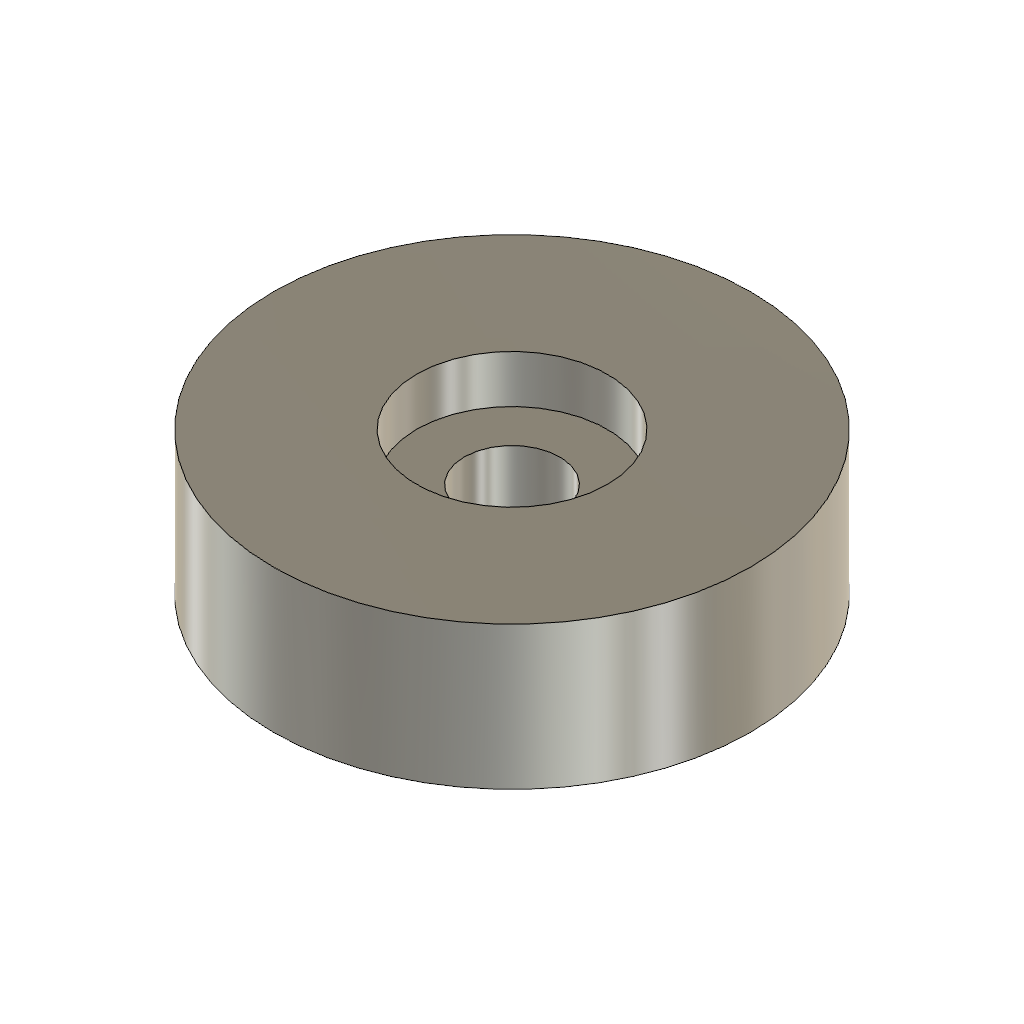
vendor_MultiDiscPart (Autodesk Fusion 360 design; units mm, degrees)
Autodesk Fusion 360 part; units mm, degrees
sketch "Disc sketch" plane through (0, 0, 0) normal (0, 0, 1) x (1, 0, 0)
  circle A0 centre (0, 0) radius 20
extrude "Disc extrude" add sketch "Disc sketch" along normal blind 12
sketch "Pocket sketch" plane through (0, 0, 0) normal (0, 0, 1) x (1, 0, 0)
  circle A0 centre (12, 0) radius 3
extrude "Pocket extrude" cut sketch "Pocket sketch" along normal blind 6
pattern_circular "Pocket ring" count 6 over 360 about axis through (0, 0, 0) along (0, 0, 1) of "Pocket extrude"
hole "Center bore" at (0, 0, 12) direction (0, 0, -1) diameter 8 end through all counterbore diameter 16 counterbore depth 4
equation "height = 20.0 mm"
